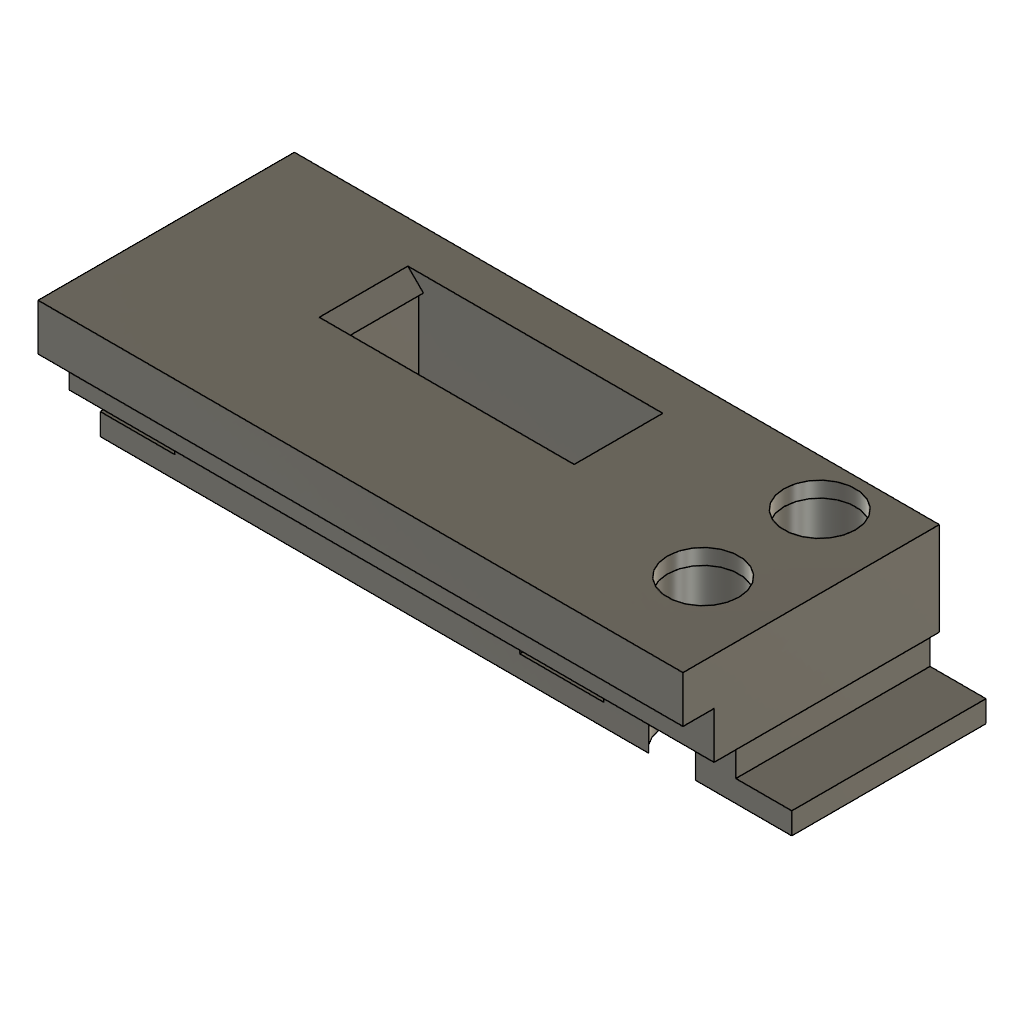
W48-usb-c (Autodesk Fusion 360 design; units mm, degrees)
Autodesk Fusion 360 part; units mm, degrees
sketch "Skizze1" plane through (0, 0, 0) normal (0, 0, 1) x (1, 0, 0)
  line L0 (-15, 0) -> (26.5, 0)
  line L1 (26.5, 0) -> (26.5, 16.5)
  line L2 (26.5, 16.5) -> (-15, 16.5)
  line L3 (-15, 16.5) -> (-15, 0)
  dimension "d1" = 41.5
  dimension "d2" = 16.5
  constraint horizontal L0
  constraint vertical L1
  constraint horizontal L2
  constraint vertical L3
  measures "d1" distance of L0.start L0.end
  measures "d2" distance of L0.start L2.end
extrude "Extrusion1" add sketch "Skizze1" along normal blind 9.6
box "Grundkörper Quader1" cut length 6.6 width 2 height -41.7 placed x (0, 0, 1) y (0, -1, 0) z (1, 0, 0) at (26.5, 2, 0)
box "Grundkörper Quader2" cut length 2.2 width 4.8 height -15 placed x (0, 0, -1) y (-1, 0, 0) z (0, 1, 0) at (-10.2, 16.5, 3.6)
box "Grundkörper Quader4" cut length 2.2 width 5.4 height -15 placed x (0, 0, -1) y (-1, 0, 0) z (0, 1, 0) at (17.4, 16.5, 3.6)
box "Grundkörper Quader6" cut length 5.7 width 15 height -13 placed x (0, 1, 0) y (-1, 0, 0) z (0, 0, 1) at (10.7, 8.1, 9.6)
box "Grundkörper Quader10" add length 3 width 14.5 height 3 placed x (0, 0, -1) y (0, 1, 0) z (1, 0, 0) at (26.5, 2, 3)
box "Grundkörper Quader5" cut length 2.2 width 9 height -15 placed x (0, 0, 1) y (1, 0, 0) z (0, 1, 0) at (25.9, 16.5, 1.4)
box "Grundkörper Quader11" cut length 3.6 width 2 height -47 placed x (0, 0, -1) y (0, -1, 0) z (-1, 0, 0) at (-15, 4, 3.6)
hole "Bohrung1" at (21.8, 13.5, 9.6) direction (0, 0, -1) diameter 4.6 depth 10 tip angle 118
hole "Bohrung2" at (21.8, 6, 9.6) direction (0, 0, -1) diameter 4.6 depth 10 tip angle 118
hole "Bohrung3" at (21.8, 12.3693, 0) direction (0, 0, 1) diameter 5 depth 8.6 tip angle 180
hole "Bohrung4" at (21.8, 6.956, 0) direction (0, 0, 1) diameter 5 depth 8.6 tip angle 180
box "Grundkörper Quader12" add length 1 width 5.7 height 0.3 placed x (0, 0, -1) y (0, 1, 0) z (1, 0, 0) at (-4.3, 8.1, 9.6)
box "Grundkörper Quader13" add length 1 width 5.7 height 0.3 placed x (0, 0, -1) y (0, -1, 0) z (-1, 0, 0) at (10.7, 13.8, 9.6)
chamfer "Fase2" distance 1 distance2 1 1 edges at (-4, 10.95, 9.6) measured on face at (-4, 11.9, 9.2667)
chamfer "Fase3" distance 1 distance2 1 1 edges at (10.4, 10.95, 9.6) measured on face at (10.4, 10, 9.2667)
